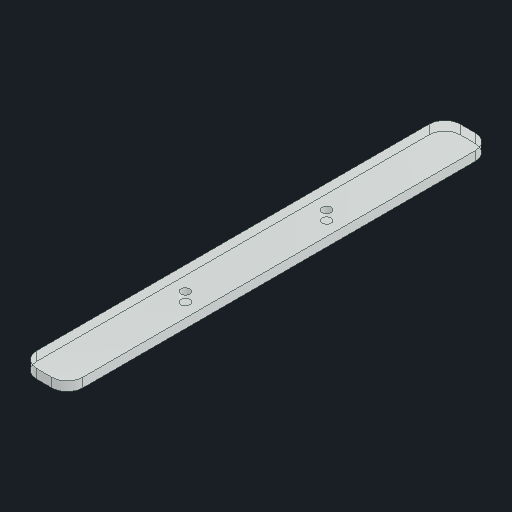
# Autodesk Inventor part: 7_6_6_girophare
Saved by Autodesk Inventor 2026 (Build 300175000, 175)
## iProperties
Created: 2025-06-22
Part Number: 7_6_6_girophare
Material: Glass
Document SubType Name: Modeling
Designer: remg9
Density: 2.18 g/cm^3
Appearance: Clear
Author: remg9
Autodesk Inventor part; units mm, degrees
ref_plane "YZ Plane" through (0, 0, 0) normal (1, 0, 0) x (0, 1, 0)
ref_plane "XZ Plane" through (0, 0, 0) normal (0, 1, 0) x (-1, 0, 0)
ref_plane "XY Plane" through (0, 0, 0) normal (0, 0, 1) x (1, 0, 0)
sketch "Sketch1" plane through (0, 0, 0) normal (0, 1, 0) x (-1, 0, 0)
  line L0 (0, 0) -> (15, 0)
  line L1 (15, 0) -> (15, -138)
  line L2 (15, -138) -> (0, -138)
  line L3 (0, -138) -> (0, 0)
  dimension "d0" = 138
  dimension "d1" = 15
  constraints: 8 end point, 2 parallel, 1 horizontal, 1 perpendicular
  measures "d0" distance of L0.end L1.end
  measures "d1" distance of L1.end L2.end
extrude "Extrusion1" add sketch "Sketch1" along normal blind 3
fillet "Fillet1" radius 5 4 edges at (0, 1.5, 0) (-15, 1.5, 0) (0, 1.5, -138) (-15, 1.5, -138)
sketch "Sketch2" plane through (0, 3, 0) normal (0, 1, 0) x (1, 0, 0)
  line L0 (-7.5, 0) -> (-7.5, 138) construction
  line L1 (-10, 0) -> (-5, 0) construction
  line L2 (-5, 138) -> (-10, 138) construction
  point P0 (0, 0)
  point P1 (-7.5, 46)
  point P2 (-7.5, 92)
  dimension "d5" = 46
  dimension "d6" = 46
  dimension "d7" = 46
  constraints: 4 midpoint, 2 end point, 2 point on line, 1 vertical
  measures "d5" distance of point (-7.5, 0) point (-7.5, 46)
  measures "d6" distance of point (-7.5, 138) point (-7.5, 92)
  measures "d7" distance of point (-7.5, 46) point (-7.5, 92)
hole "Hole1" at (-7.5, 3, -46) at (-7.5, 3, -92) direction (0, -1, 0) diameter 3 end through all
body "Solid1"
